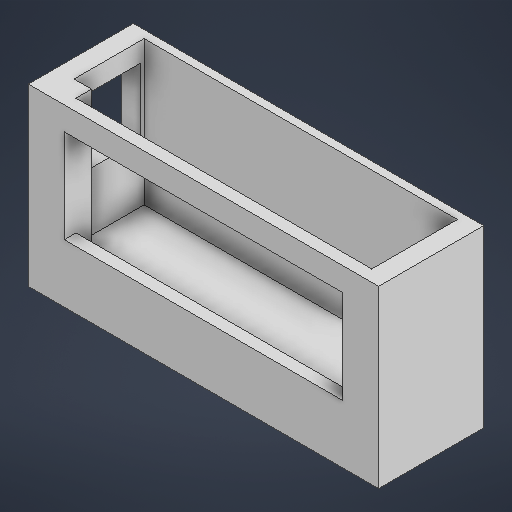
# Autodesk Inventor part: ekranik
Saved by Autodesk Inventor 2026.1 (Build 301233020, 233B)
## iProperties
Created: 2026-07-06
Part Number: ekranik
Material: Ogólny
Document SubType Name: Modeling
Designer: Bronh
Density: 1 g/cm^3
Appearance: Domyślna
Author: Bronh
Autodesk Inventor part; units mm, degrees
ref_plane "YZ Plane" through (0, 0, 0) normal (1, 0, 0) x (0, 1, 0)
ref_plane "XZ Plane" through (0, 0, 0) normal (0, 1, 0) x (-1, 0, 0)
ref_plane "XY Plane" through (0, 0, 0) normal (0, 0, 1) x (1, 0, 0)
sketch "Szkic1" plane through (0, 0, 0) normal (0, 0, 1) x (1, 0, 0)
  line L0 (45, -22.5) -> (-45, -22.5)
  line L1 (-45, -22.5) -> (-45, 22.5)
  line L2 (-45, 22.5) -> (45, 22.5)
  line L3 (45, 22.5) -> (45, -22.5)
  line L4 (45, -22.5) -> (-45, 22.5) construction
  line L5 (-45, -22.5) -> (45, 22.5) construction
  point P0 (0, 0)
  dimension "d0" = 90
  dimension "d1" = 45
  constraints: 12 end point, 2 midpoint, 2 parallel, 1 horizontal, 1 perpendicular
  measures "d0" distance of L1.end L2.end
  measures "d1" distance of L0.end L1.end
extrude "Wyciągnięcie proste1" add sketch "Szkic1" along normal blind 27
sketch "Szkic2" plane through (-45, 22.5, 0) normal (0, 1, 0) x (1, 0, 0)
  line L0 (4.75, -2) -> (85.25, -2)
  line L1 (85.25, -2) -> (85.25, -20)
  line L2 (85.25, -20) -> (4.75, -20)
  line L3 (4.75, -20) -> (4.75, -2)
  line L4 (9.25, -20) -> (85.25, -20)
  line L5 (85.25, -20) -> (85.25, -24)
  line L6 (85.25, -24) -> (9.25, -24)
  line L7 (9.25, -24) -> (9.25, -20)
  line L8 (90, -27) -> (0, -27) projected
  line L9 (0, 0) -> (0, -27) projected
  point P0 (45, 0)
  point P1 (80.5, -17)
  dimension "d4" = 80.5
  dimension "d5" = 18
  dimension "d11" = 4
  dimension "d12" = 3
  dimension "d13" = 4.75
  dimension "d28" = 76
  constraints: 16 end point, 4 parallel, 2 horizontal, 2 perpendicular, 2 point on line
  measures "d4" distance of L1.end L2.end
  measures "d5" distance of L0.end L1.end
  measures "d11" distance of L6.end L4.start
  measures "d12" distance between parallel lines of L8 L6
  measures "d13" distance between parallel lines of L9 L3
  measures "d28" distance of L5.end L6.end
extrude "Wyciągnięcie proste2" cut sketch "Szkic2" against normal blind 37
sketch "Szkic3" plane through (0, 0, 27) normal (0, 0, 1) x (1, 0, 0)
  line L0 (45, 22.5) -> (-45, 22.5) construction
  line L1 (-35.75, 16.5) -> (35.75, 16.5) construction
  line L2 (35.75, 16.5) -> (35.75, -7.5) construction
  line L3 (35.75, -7.5) -> (-35.75, -7.5) construction
  line L4 (-35.75, -7.5) -> (-35.75, 16.5) construction
  line L5 (-35.75, 16.5) -> (35.75, 16.5)
  line L6 (35.75, 16.5) -> (35.75, -7.5)
  line L7 (35.75, -7.5) -> (-35.75, -7.5)
  line L8 (-35.75, -7.5) -> (-35.75, 16.5)
  line L9 (-45, 22.5) -> (-45, -22.5) projected
  point P0 (0, 0)
  dimension "d16" = 71.5
  dimension "d17" = 24
  dimension "d18" = 6
  dimension "d19" = 9.25
  constraints: 16 end point, 4 parallel, 2 horizontal, 2 perpendicular
  measures "d16" distance of L2.end L3.end
  measures "d17" distance of L1.end L2.end
  measures "d18" distance between parallel lines of L0 L1
  measures "d19" distance between parallel lines of L9 L4
extrude "Wyciągnięcie proste3" cut sketch "Szkic3" against normal blind 3
sketch "Szkic4" plane through (-45, -22.5, 0) normal (-1, 0, 0) x (0, 0, 1)
  line L0 (3, 40) -> (20, 40)
  line L1 (20, 40) -> (20, 23)
  line L2 (20, 23) -> (3, 23)
  line L3 (3, 23) -> (3, 40)
  line L4 (0, 0) -> (27, 0) projected
  line L5 (0, 45) -> (0, 0) projected
  point P0 (0, 22.5)
  dimension "d22" = 17
  dimension "d23" = 17
  dimension "d24" = 23
  dimension "d25" = 3
  constraints: 8 end point, 2 parallel, 1 horizontal, 1 perpendicular
  measures "d22" distance of L1.end L2.end
  measures "d23" distance of L0.end L1.end
  measures "d24" distance between parallel lines of L4 L2
  measures "d25" distance between parallel lines of L5 L3
extrude "Wyciągnięcie proste4" cut sketch "Szkic4" against normal blind 5
